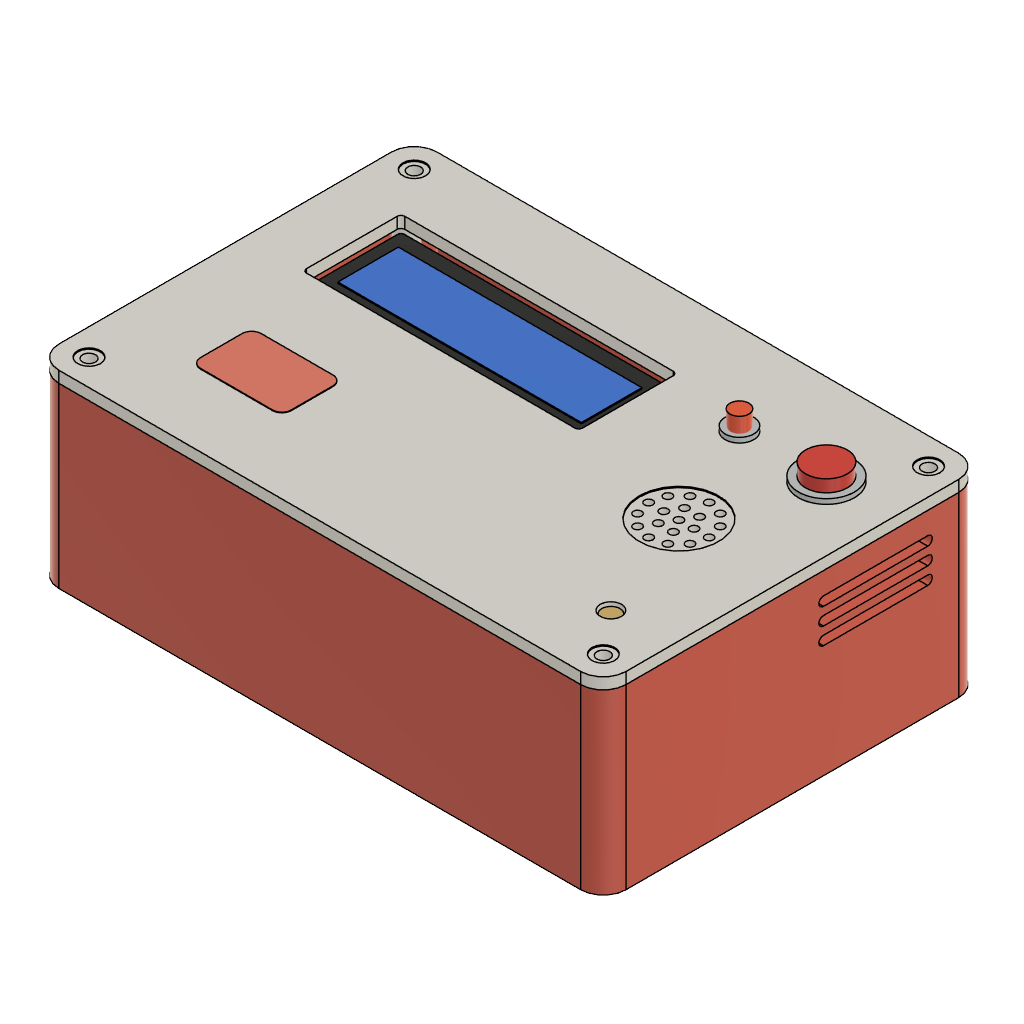
Pomodoro_Box (Autodesk Fusion 360 design; units mm, degrees)
part number: 2026-11-12-20-58-02-646
Autodesk Fusion 360 part; units mm, degrees
sketch "Sk_Vien_Ngoai_150x100" plane through (0, 0, 0) normal (0, 0, 1) x (1, 0, 0)
  line L0 (6, 0) -> (144, 0)
  line L1 (150, 6) -> (150, 94)
  line L2 (144, 100) -> (6, 100)
  line L3 (0, 94) -> (0, 6)
  arc A0 (144, 0) -> (150, 6) centre (144, 6) ccw
  arc A1 (150, 94) -> (144, 100) centre (144, 94) ccw
  arc A2 (6, 100) -> (0, 94) centre (6, 94) ccw
  arc A3 (0, 6) -> (6, 0) centre (6, 6) ccw
  constraint tangent L0 A0
  constraint tangent L1 A0
  constraint tangent L1 A1
  constraint tangent L2 A1
  constraint tangent L2 A2
  constraint tangent L3 A2
  constraint tangent L3 A3
  constraint tangent L0 A3
extrude "Extrude1" add sketch "Sk_Vien_Ngoai_150x100" along normal blind 47 makes body 1
sketch "Sk_Long_Hop_145x95" plane through (0, 0, 0) normal (0, 0, 1) x (1, 0, 0)
  line L0 (6, 2.5) -> (144, 2.5)
  line L1 (147.5, 6) -> (147.5, 94)
  line L2 (144, 97.5) -> (6, 97.5)
  line L3 (2.5, 94) -> (2.5, 6)
  arc A0 (144, 2.5) -> (147.5, 6) centre (144, 6) ccw
  arc A1 (147.5, 94) -> (144, 97.5) centre (144, 94) ccw
  arc A2 (6, 97.5) -> (2.5, 94) centre (6, 94) ccw
  arc A3 (2.5, 6) -> (6, 2.5) centre (6, 6) ccw
  constraint tangent L0 A0
  constraint tangent L1 A0
  constraint tangent L1 A1
  constraint tangent L2 A1
  constraint tangent L2 A2
  constraint tangent L3 A2
  constraint tangent L3 A3
  constraint tangent L0 A3
extrude "Extrude2" cut sketch "Sk_Long_Hop_145x95" along normal blind 45.5 from surface at 2.5 bodies 1
sketch "Sk_4_Tru_Vit_M3_D9" plane through (0, 0, 0) normal (0, 0, 1) x (1, 0, 0)
  circle A0 centre (7, 7) radius 4.5
  circle A1 centre (143, 7) radius 4.5
  circle A2 centre (7, 93) radius 4.5
  circle A3 centre (143, 93) radius 4.5
extrude "Extrude3" add sketch "Sk_4_Tru_Vit_M3_D9" along normal blind 44.5 from surface at 2.5 bodies 1
sketch "Sk_4_Lo_Ren_M3_D2_5" plane through (0, 0, 0) normal (0, 0, 1) x (1, 0, 0)
  circle A0 centre (7, 7) radius 1.25
  circle A1 centre (143, 7) radius 1.25
  circle A2 centre (7, 93) radius 1.25
  circle A3 centre (143, 93) radius 1.25
extrude "Extrude4" cut sketch "Sk_4_Lo_Ren_M3_D2_5" along normal blind 42.5 from surface at 5 bodies 1
sketch "Sk_Mat_Sau_USB_JackDC" plane through (0, 0, 0) normal (0, 1, 0) x (1, 0, 0)
  line L0 (121.5, -18.5) -> (130.5, -18.5)
  line L1 (132.5, -20.5) -> (132.5, -25.5)
  line L2 (130.5, -27.5) -> (121.5, -27.5)
  line L3 (119.5, -25.5) -> (119.5, -20.5)
  arc A0 (132.5, -20.5) -> (130.5, -18.5) centre (130.5, -20.5) ccw
  arc A1 (130.5, -27.5) -> (132.5, -25.5) centre (130.5, -25.5) ccw
  arc A2 (119.5, -25.5) -> (121.5, -27.5) centre (121.5, -25.5) ccw
  arc A3 (121.5, -18.5) -> (119.5, -20.5) centre (121.5, -20.5) ccw
  circle A4 centre (30, -16) radius 4
  constraint tangent L0 A0
  constraint tangent L1 A0
  constraint tangent L1 A1
  constraint tangent L2 A1
  constraint tangent L2 A2
  constraint tangent L3 A2
  constraint tangent L3 A3
  constraint tangent L0 A3
extrude "Extrude5" cut sketch "Sk_Mat_Sau_USB_JackDC" along normal blind 7 from surface at 95 bodies 1
sketch "Sk_Mat_Trai_5_Khe_DHT22" plane through (0, 0, 0) normal (1, 0, 0) x (0, 0, -1)
  line L0 (-7.8, 53.2) -> (-7.8, 80.8)
  line L1 (-10.2, 80.8) -> (-10.2, 53.2)
  arc A0 (-7.8, 80.8) -> (-10.2, 80.8) centre (-9, 80.8) ccw
  arc A1 (-10.2, 53.2) -> (-7.8, 53.2) centre (-9, 53.2) ccw
  line L2 (-12.3, 53.2) -> (-12.3, 80.8)
  line L3 (-14.7, 80.8) -> (-14.7, 53.2)
  arc A2 (-12.3, 80.8) -> (-14.7, 80.8) centre (-13.5, 80.8) ccw
  arc A3 (-14.7, 53.2) -> (-12.3, 53.2) centre (-13.5, 53.2) ccw
  line L4 (-16.8, 53.2) -> (-16.8, 80.8)
  line L5 (-19.2, 80.8) -> (-19.2, 53.2)
  arc A4 (-16.8, 80.8) -> (-19.2, 80.8) centre (-18, 80.8) ccw
  arc A5 (-19.2, 53.2) -> (-16.8, 53.2) centre (-18, 53.2) ccw
  line L6 (-21.3, 53.2) -> (-21.3, 80.8)
  line L7 (-23.7, 80.8) -> (-23.7, 53.2)
  arc A6 (-21.3, 80.8) -> (-23.7, 80.8) centre (-22.5, 80.8) ccw
  arc A7 (-23.7, 53.2) -> (-21.3, 53.2) centre (-22.5, 53.2) ccw
  line L8 (-25.8, 53.2) -> (-25.8, 80.8)
  line L9 (-28.2, 80.8) -> (-28.2, 53.2)
  arc A8 (-25.8, 80.8) -> (-28.2, 80.8) centre (-27, 80.8) ccw
  arc A9 (-28.2, 53.2) -> (-25.8, 53.2) centre (-27, 53.2) ccw
extrude "Extrude6" cut sketch "Sk_Mat_Trai_5_Khe_DHT22" along normal blind 6 from surface at -1 bodies 1
sketch "Sk_Mat_Phai_3_Khe_Thoat_Nhiet" plane through (0, 0, 0) normal (1, 0, 0) x (0, 0, -1)
  line L0 (-29.8, 58.2) -> (-29.8, 85.8)
  line L1 (-32.2, 85.8) -> (-32.2, 58.2)
  arc A0 (-29.8, 85.8) -> (-32.2, 85.8) centre (-31, 85.8) ccw
  arc A1 (-32.2, 58.2) -> (-29.8, 58.2) centre (-31, 58.2) ccw
  line L2 (-34.3, 58.2) -> (-34.3, 85.8)
  line L3 (-36.7, 85.8) -> (-36.7, 58.2)
  arc A2 (-34.3, 85.8) -> (-36.7, 85.8) centre (-35.5, 85.8) ccw
  arc A3 (-36.7, 58.2) -> (-34.3, 58.2) centre (-35.5, 58.2) ccw
  line L4 (-38.8, 58.2) -> (-38.8, 85.8)
  line L5 (-41.2, 85.8) -> (-41.2, 58.2)
  arc A4 (-38.8, 85.8) -> (-41.2, 85.8) centre (-40, 85.8) ccw
  arc A5 (-41.2, 58.2) -> (-38.8, 58.2) centre (-40, 58.2) ccw
extrude "Extrude7" cut sketch "Sk_Mat_Phai_3_Khe_Thoat_Nhiet" along normal blind 6 from surface at 145 bodies 1
sketch "Sk_Nap_Hop_150x100" plane through (0, 0, 0) normal (0, 0, 1) x (1, 0, 0)
  line L0 (6, 0) -> (144, 0)
  line L1 (150, 6) -> (150, 94)
  line L2 (144, 100) -> (6, 100)
  line L3 (0, 94) -> (0, 6)
  arc A0 (144, 0) -> (150, 6) centre (144, 6) ccw
  arc A1 (150, 94) -> (144, 100) centre (144, 94) ccw
  arc A2 (6, 100) -> (0, 94) centre (6, 94) ccw
  arc A3 (0, 6) -> (6, 0) centre (6, 6) ccw
  constraint tangent L0 A0
  constraint tangent L1 A0
  constraint tangent L1 A1
  constraint tangent L2 A1
  constraint tangent L2 A2
  constraint tangent L3 A2
  constraint tangent L3 A3
  constraint tangent L0 A3
extrude "Extrude8" add sketch "Sk_Nap_Hop_150x100" along normal blind 3 from surface at 47 separate body makes body 2
sketch "Sk_Cua_So_LCD_73x26" plane through (0, 0, 0) normal (0, 0, 1) x (1, 0, 0)
  line L0 (16.5, 55) -> (87.5, 55)
  line L1 (88.5, 56) -> (88.5, 80)
  line L2 (87.5, 81) -> (16.5, 81)
  line L3 (15.5, 80) -> (15.5, 56)
  arc A0 (87.5, 55) -> (88.5, 56) centre (87.5, 56) ccw
  arc A1 (88.5, 80) -> (87.5, 81) centre (87.5, 80) ccw
  arc A2 (16.5, 81) -> (15.5, 80) centre (16.5, 80) ccw
  arc A3 (15.5, 56) -> (16.5, 55) centre (16.5, 56) ccw
  constraint tangent L0 A0
  constraint tangent L1 A0
  constraint tangent L1 A1
  constraint tangent L2 A1
  constraint tangent L2 A2
  constraint tangent L3 A2
  constraint tangent L3 A3
  constraint tangent L0 A3
extrude "Extrude9" cut sketch "Sk_Cua_So_LCD_73x26" along normal blind 4 from surface at 46.5 bodies 2
sketch "Sk_Cac_Lo_Tron_Tren_Nap" plane through (0, 0, 0) normal (0, 0, 1) x (1, 0, 0)
  circle A0 centre (7, 7) radius 1.7
  circle A1 centre (143, 7) radius 1.7
  circle A2 centre (7, 93) radius 1.7
  circle A3 centre (143, 93) radius 1.7
  circle A4 centre (133, 76) radius 6.1
  circle A5 centre (110, 76) radius 3
  circle A6 centre (134, 18) radius 2.8
  circle A7 centre (122, 48) radius 1.1
  circle A8 centre (126, 48) radius 1.1
  circle A9 centre (124, 51.4641) radius 1.1
  circle A10 centre (120, 51.4641) radius 1.1
  circle A11 centre (118, 48) radius 1.1
  circle A12 centre (120, 44.5359) radius 1.1
  circle A13 centre (124, 44.5359) radius 1.1
  circle A14 centre (130, 48) radius 1.1
  circle A15 centre (128.9282, 52) radius 1.1
  circle A16 centre (126, 54.9282) radius 1.1
  circle A17 centre (122, 56) radius 1.1
  circle A18 centre (118, 54.9282) radius 1.1
  circle A19 centre (115.0718, 52) radius 1.1
  circle A20 centre (114, 48) radius 1.1
  circle A21 centre (115.0718, 44) radius 1.1
  circle A22 centre (118, 41.0718) radius 1.1
  circle A23 centre (122, 40) radius 1.1
  circle A24 centre (126, 41.0718) radius 1.1
  circle A25 centre (128.9282, 44) radius 1.1
extrude "Extrude10" cut sketch "Sk_Cac_Lo_Tron_Tren_Nap" along normal blind 4 from surface at 46.5 bodies 2
sketch "Sk_Vi_Sa_Loa_Va_Vit" plane through (0, 0, 0) normal (0, 0, 1) x (1, 0, 0)
  circle A0 centre (122, 48) radius 10.5
  circle A1 centre (7, 7) radius 3
  circle A2 centre (143, 7) radius 3
  circle A3 centre (7, 93) radius 3
  circle A4 centre (143, 93) radius 3
extrude "Extrude11" cut sketch "Sk_Vi_Sa_Loa_Va_Vit" along normal blind 0.5 from surface at 49.7 bodies 2
sketch "Sk_Vung_Quet_The_52x34" plane through (0, 0, 0) normal (0, 0, 1) x (1, 0, 0)
  line L0 (24.5, 19) -> (43.5, 19)
  line L1 (46, 21.5) -> (46, 32.5)
  line L2 (43.5, 35) -> (24.5, 35)
  line L3 (22, 32.5) -> (22, 21.5)
  arc A0 (43.5, 19) -> (46, 21.5) centre (43.5, 21.5) ccw
  arc A1 (46, 32.5) -> (43.5, 35) centre (43.5, 32.5) ccw
  arc A2 (24.5, 35) -> (22, 32.5) centre (24.5, 32.5) ccw
  arc A3 (22, 21.5) -> (24.5, 19) centre (24.5, 21.5) ccw
  constraint tangent L0 A0
  constraint tangent L1 A0
  constraint tangent L1 A1
  constraint tangent L2 A1
  constraint tangent L2 A2
  constraint tangent L3 A2
  constraint tangent L3 A3
  constraint tangent L0 A3
extrude "Extrude12" add sketch "Sk_Vung_Quet_The_52x34" along normal blind 0.15 from surface at 50 separate body makes body 3
sketch "Sk_4_Cot_Do_LCD_Dai_7mm" plane through (0, 0, 0) normal (0, 0, 1) x (1, 0, 0)
  circle A0 centre (14.5, 52.5) radius 2.75
  circle A1 centre (89.5, 52.5) radius 2.75
  circle A2 centre (14.5, 83.5) radius 2.75
  circle A3 centre (89.5, 83.5) radius 2.75
extrude "Extrude13" add sketch "Sk_4_Cot_Do_LCD_Dai_7mm" along normal blind 7 from surface at 40 bodies 2
sketch "Sk_4_Chan_Cao_Su" plane through (0, 0, 0) normal (0, 0, 1) x (1, 0, 0)
  circle A0 centre (14, 12) radius 5
  circle A1 centre (136, 12) radius 5
  circle A2 centre (14, 88) radius 5
  circle A3 centre (136, 88) radius 5
extrude "Extrude14" add sketch "Sk_4_Chan_Cao_Su" along normal blind 2 from surface at -2 separate body makes body 4 at (13.2912, 91.8668, -2) makes body 5 at (136.6089, 10.4485, -2) makes body 6 at (14.6089, 10.4485, -2) makes body 7 at (137.0391, 86.2001, -2)
sketch "Sk_4_Cot_Dong_Cao_5mm" plane through (0, 0, 0) normal (0, 0, 1) x (1, 0, 0)
  circle A0 centre (78, 49) radius 2
  circle A1 centre (142, 49) radius 2
  circle A2 centre (78, 93) radius 2
  circle A3 centre (142, 93) radius 2
extrude "Extrude15" add sketch "Sk_4_Cot_Dong_Cao_5mm" along normal blind 5 from surface at 2.5 separate body makes body 8 at (79.9382, 92.5065, 5.8333) makes body 9 at (143.3234, 50.4996, 5.8333) makes body 10 at (79.3234, 50.4996, 5.8333) makes body 11 at (143.3234, 94.4996, 5.8333)
sketch "Sk_Board_Duc_Lo_70x50" plane through (0, 0, 0) normal (0, 0, 1) x (1, 0, 0)
  line L0 (75, 46) -> (145, 46)
  line L1 (145, 46) -> (145, 96)
  line L2 (145, 96) -> (75, 96)
  line L3 (75, 96) -> (75, 46)
extrude "Extrude16" add sketch "Sk_Board_Duc_Lo_70x50" along normal blind 1.6 from surface at 7.5 separate body makes body 12
sketch "Sk_ESP32_Headers" plane through (0, 0, 0) normal (0, 0, 1) x (1, 0, 0)
  line L0 (113, 48) -> (115.5, 48)
  line L1 (115.5, 48) -> (115.5, 94)
  line L2 (115.5, 94) -> (113, 94)
  line L3 (113, 94) -> (113, 48)
  line L4 (136.5, 48) -> (139, 48)
  line L5 (139, 48) -> (139, 94)
  line L6 (139, 94) -> (136.5, 94)
  line L7 (136.5, 94) -> (136.5, 48)
extrude "Extrude17" add sketch "Sk_ESP32_Headers" along normal blind 8.4 from surface at 9.1 separate body makes body 13 at (113, 78.6667, 11.9) makes body 14 at (136.5, 78.6667, 11.9)
sketch "Sk_ESP32_PCB" plane through (0, 0, 0) normal (0, 0, 1) x (1, 0, 0)
  line L0 (113, 45.5) -> (139, 45.5)
  line L1 (140, 46.5) -> (140, 96)
  line L2 (139, 97) -> (113, 97)
  line L3 (112, 96) -> (112, 46.5)
  arc A0 (139, 45.5) -> (140, 46.5) centre (139, 46.5) ccw
  arc A1 (140, 96) -> (139, 97) centre (139, 96) ccw
  arc A2 (113, 97) -> (112, 96) centre (113, 96) ccw
  arc A3 (112, 46.5) -> (113, 45.5) centre (113, 46.5) ccw
  constraint tangent L0 A0
  constraint tangent L1 A0
  constraint tangent L1 A1
  constraint tangent L2 A1
  constraint tangent L2 A2
  constraint tangent L3 A2
  constraint tangent L3 A3
  constraint tangent L0 A3
extrude "Extrude18" add sketch "Sk_ESP32_PCB" along normal blind 1.6 from surface at 17.5 separate body makes body 15
sketch "Sk_ESP32_WROOM_Shield" plane through (0, 0, 0) normal (0, 0, 1) x (1, 0, 0)
  line L0 (117, 52) -> (135, 52)
  line L1 (135, 52) -> (135, 78)
  line L2 (135, 78) -> (117, 78)
  line L3 (117, 78) -> (117, 52)
extrude "Extrude19" add sketch "Sk_ESP32_WROOM_Shield" along normal blind 3.2 from surface at 19.1 separate body makes body 16
sketch "Sk_ESP32_MicroUSB" plane through (0, 0, 0) normal (0, 0, 1) x (1, 0, 0)
  line L0 (122, 92) -> (130, 92)
  line L1 (130, 92) -> (130, 98.5)
  line L2 (130, 98.5) -> (122, 98.5)
  line L3 (122, 98.5) -> (122, 92)
extrude "Extrude20" add sketch "Sk_ESP32_MicroUSB" along normal blind 3 from surface at 19.1 separate body makes body 17
sketch "Sk_DHT22_Gia_Chu_L" plane through (0, 0, 0) normal (0, 0, 1) x (1, 0, 0)
  line L0 (5, 58.5) -> (16, 58.5)
  line L1 (16, 58.5) -> (16, 75.5)
  line L2 (16, 75.5) -> (5, 75.5)
  line L3 (5, 75.5) -> (5, 58.5)
extrude "Extrude21" add sketch "Sk_DHT22_Gia_Chu_L" along normal blind 2.5 from surface at 2.5 separate body makes body 18
sketch "Sk_DHT22_Module" plane through (0, 0, 0) normal (0, 0, 1) x (1, 0, 0)
  line L0 (9.5, 59.5) -> (11.2, 59.5)
  line L1 (11.2, 59.5) -> (11.2, 74.5)
  line L2 (11.2, 74.5) -> (9.5, 74.5)
  line L3 (9.5, 74.5) -> (9.5, 59.5)
extrude "Extrude22" add sketch "Sk_DHT22_Module" along normal blind 25 from surface at 5 separate body makes body 19
sketch "Sk_DHT22_Sensor" plane through (0, 0, 0) normal (0, 0, 1) x (1, 0, 0)
  line L0 (3.8, 59.5) -> (9.5, 59.5)
  line L1 (9.5, 59.5) -> (9.5, 74.5)
  line L2 (9.5, 74.5) -> (3.8, 74.5)
  line L3 (3.8, 74.5) -> (3.8, 59.5)
extrude "Extrude23" add sketch "Sk_DHT22_Sensor" along normal blind 20 from surface at 8 separate body makes body 20
sketch "Sk_Jack_DC_5V" plane through (0, 0, 0) normal (0, 1, 0) x (1, 0, 0)
  circle A0 centre (30, -16) radius 3.9
extrude "Extrude24" add sketch "Sk_Jack_DC_5V" along normal blind 16.2 from surface at 85 separate body makes body 21
sketch "Sk_Jack_DC_5V_Collar" plane through (0, 0, 0) normal (0, 1, 0) x (1, 0, 0)
  circle A0 centre (30, -16) radius 5.4
extrude "Extrude25" add sketch "Sk_Jack_DC_5V_Collar" along normal blind 1.5 from surface at 100 separate body makes body 22
sketch "Sk_LCD1602_PCB_80x36" plane through (0, 0, 0) normal (0, 0, 1) x (1, 0, 0)
  line L0 (12, 50) -> (92, 50)
  line L1 (92, 50) -> (92, 86)
  line L2 (92, 86) -> (12, 86)
  line L3 (12, 86) -> (12, 50)
extrude "Extrude26" add sketch "Sk_LCD1602_PCB_80x36" along normal blind 1.6 from surface at 38.4 separate body makes body 23
sketch "Sk_LCD1602_Khung_Den" plane through (0, 0, 0) normal (0, 0, 1) x (1, 0, 0)
  line L0 (17.3, 56) -> (86.7, 56)
  line L1 (87.5, 56.8) -> (87.5, 79.2)
  line L2 (86.7, 80) -> (17.3, 80)
  line L3 (16.5, 79.2) -> (16.5, 56.8)
  arc A0 (86.7, 56) -> (87.5, 56.8) centre (86.7, 56.8) ccw
  arc A1 (87.5, 79.2) -> (86.7, 80) centre (86.7, 79.2) ccw
  arc A2 (17.3, 80) -> (16.5, 79.2) centre (17.3, 79.2) ccw
  arc A3 (16.5, 56.8) -> (17.3, 56) centre (17.3, 56.8) ccw
  constraint tangent L0 A0
  constraint tangent L1 A0
  constraint tangent L1 A1
  constraint tangent L2 A1
  constraint tangent L2 A2
  constraint tangent L3 A2
  constraint tangent L3 A3
  constraint tangent L0 A3
extrude "Extrude27" add sketch "Sk_LCD1602_Khung_Den" along normal blind 6.8 from surface at 40 separate body makes body 24
sketch "Sk_LCD1602_Man_Hinh" plane through (0, 0, 0) normal (0, 0, 1) x (1, 0, 0)
  line L0 (19.8, 60) -> (84.2, 60)
  line L1 (84.2, 60) -> (84.2, 76)
  line L2 (84.2, 76) -> (19.8, 76)
  line L3 (19.8, 76) -> (19.8, 60)
extrude "Extrude28" add sketch "Sk_LCD1602_Man_Hinh" along normal blind 0.3 from surface at 46.8 separate body makes body 25
sketch "Sk_LCD1602_Module_I2C" plane through (0, 0, 0) normal (0, 0, 1) x (1, 0, 0)
  line L0 (18, 58) -> (60, 58)
  line L1 (60, 58) -> (60, 77)
  line L2 (60, 77) -> (18, 77)
  line L3 (18, 77) -> (18, 58)
extrude "Extrude29" add sketch "Sk_LCD1602_Module_I2C" along normal blind 3.4 from surface at 35 separate body makes body 26
sketch "Sk_RFID_RC522_60x40" plane through (0, 0, 0) normal (0, 0, 1) x (1, 0, 0)
  line L0 (22, 6) -> (82, 6)
  line L1 (82, 6) -> (82, 46)
  line L2 (82, 46) -> (22, 46)
  line L3 (22, 46) -> (22, 6)
extrude "Extrude30" add sketch "Sk_RFID_RC522_60x40" along normal blind 1.6 from surface at 44.4 separate body makes body 27
sketch "Sk_Module_Buzzer_PCB" plane through (0, 0, 0) normal (0, 0, 1) x (1, 0, 0)
  line L0 (95, 41.5) -> (128, 41.5)
  line L1 (128, 41.5) -> (128, 54.5)
  line L2 (128, 54.5) -> (95, 54.5)
  line L3 (95, 54.5) -> (95, 41.5)
extrude "Extrude31" add sketch "Sk_Module_Buzzer_PCB" along normal blind 1.6 from surface at 36 separate body makes body 28
sketch "Sk_Buzzer_Cyl_D12" plane through (0, 0, 0) normal (0, 0, 1) x (1, 0, 0)
  circle A0 centre (122, 48) radius 6
extrude "Extrude32" add sketch "Sk_Buzzer_Cyl_D12" along normal blind 9.4 from surface at 37.6 separate body makes body 29
sketch "Sk_Module_Quang_Tro_PCB" plane through (0, 0, 0) normal (0, 0, 1) x (1, 0, 0)
  line L0 (104, 11) -> (136, 11)
  line L1 (136, 11) -> (136, 25)
  line L2 (136, 25) -> (104, 25)
  line L3 (104, 25) -> (104, 11)
extrude "Extrude33" add sketch "Sk_Module_Quang_Tro_PCB" along normal blind 1.6 from surface at 39 separate body makes body 30
sketch "Sk_Quang_Tro_Dau_Doc" plane through (0, 0, 0) normal (0, 0, 1) x (1, 0, 0)
  circle A0 centre (134, 18) radius 2.4
extrude "Extrude34" add sketch "Sk_Quang_Tro_Dau_Doc" along normal blind 8.6 from surface at 40.6 separate body makes body 31
sketch "Sk_Nut_Nhan_Than_Ren" plane through (0, 0, 0) normal (0, 0, 1) x (1, 0, 0)
  circle A0 centre (133, 76) radius 5.9
extrude "Extrude35" add sketch "Sk_Nut_Nhan_Than_Ren" along normal blind 18 from surface at 32 separate body makes body 32
sketch "Sk_Nut_Nhan_Vien_Va_De_LED" plane through (0, 0, 0) normal (0, 0, 1) x (1, 0, 0)
  circle A0 centre (133, 76) radius 7.4
  circle A1 centre (110, 76) radius 3.8
extrude "Extrude36" add sketch "Sk_Nut_Nhan_Vien_Va_De_LED" along normal blind 1.3 from surface at 50 separate body makes body 33 at (133.9012, 73.4865, 50) makes body 34 at (111.0466, 75.2865, 50)
sketch "Sk_Nut_Nhan_Mu_Do" plane through (0, 0, 0) normal (0, 0, 1) x (1, 0, 0)
  circle A0 centre (133, 76) radius 5.5
extrude "Extrude37" add sketch "Sk_Nut_Nhan_Mu_Do" along normal blind 3.2 from surface at 51.3 separate body makes body 35
sketch "Sk_LED_Do_5mm" plane through (0, 0, 0) normal (0, 0, 1) x (1, 0, 0)
  circle A0 centre (110, 76) radius 2.5
extrude "Extrude38" add sketch "Sk_LED_Do_5mm" along normal blind 13.2 from surface at 42 separate body makes body 36
sketch "Sk_Jack_DC_5V_Pin" plane through (0, 0, 0) normal (0, 1, 0) x (1, 0, 0)
  circle A0 centre (30, -16) radius 1.1
extrude "Extrude39" add sketch "Sk_Jack_DC_5V_Pin" along normal blind 2.2 from surface at 99.5 separate body makes body 37
named bodies: "01_Than_Hop_BottomCase", "02_Nap_Hop_TopCover", "Bieu_Tuong_The_RFID", "Chan_Cao_Su_1", "Chan_Cao_Su_2", "Chan_Cao_Su_3", "Chan_Cao_Su_4", "Cot_Dong_M3_1", "Cot_Dong_M3_2", "Cot_Dong_M3_3", "Cot_Dong_M3_4", "Board_Duc_Lo_70x50", "ESP32_Header_1", "ESP32_Header_2", "ESP32_DevKit_V1_PCB", "ESP32_WROOM32_Shield", "ESP32_Cong_MicroUSB", "DHT22_De_Kep_L", "DHT22_PCB", "DHT22_Cam_Bien", "Jack_DC_5V_Than", "Jack_DC_5V_Vien_Ngoai", "LCD1602_PCB_Xanh", "LCD1602_Khung_Vien", "LCD1602_Man_Hinh_Hien_Thi", "LCD1602_Module_I2C", "RFID_RC522_PCB", "Buzzer_Module_PCB", "Buzzer_Chu_Dong_D12", "Quang_Tro_LM393_PCB", "Quang_Tro_Cam_Bien", "Nut_Nhan_Than_Duoi", "Vien_Giu_Nut_Va_LED_1", "Vien_Giu_Nut_Va_LED_2", "Nut_Nhan_Do_ID4", "LED_Do_5mm_ID4", "Jack_DC_5V_Chan_Giua"
